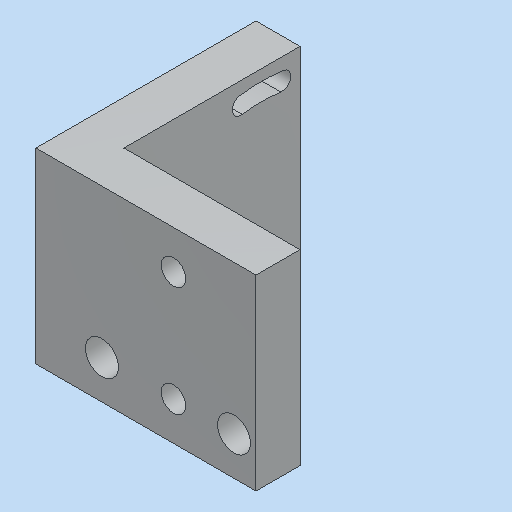
# Autodesk Inventor part: MM0948AN140_G01_118
Saved by Autodesk Inventor 2023.3 (Build 273359000, 359)
## iProperties
RuleStatus: InUse
Created: 2023-03-31
Part Number: MM0948AN140_G01_118
Material: 3.3206 AlMgSi0,5 - AW 6060
Description: =<RBPARTNOTITLE2>
Document SubType Name: Modeling
Designer: FH/Wi
Mass: 50.1036 g
Surface Area: 71.436 cm^2
Volume: 18.5569 cm^3
Density: 2.7 g/cm^3
Appearance: Aluminium AnP
AnP_Kategorie: 1
AnP_Material: =<Material>
MaxAbmaße: 34 x 40 x 40 (FM)
AnP_TemplVers: 20200821
RBDOCUMENTTYPE: DRF
RBDOCUMENTVERSION: 00
RBDRAWINGMAINSCALE: 1:1
RBDRAWINGMISSINGSPEC: --
RBDRAWINGVOLUME: --
RBDSV1: 0850
RBGBEDGESIN1: +0,5
RBGBEDGESIN2: +0,2
RBGBEDGESOUT1: -0,3
RBGBEDGESOUT2: -0,1
RBMATERIAL: =<Material>
RBMATMEETS: --
RBMATNO: =<Part Number>
RBPARTMADEOF: L 40 x 40 x 8 x 34 (FM)
RBPARTNO: SIEHE MNR
RBPARTNOTITLE1: manufactured part
RBPARTNOTITLE2: Anfertigungsteil
RBPARTSAFETYINDICATOR: --
RBSURFACE: anodised colourless
RBSURFACE2: eloxiert farblos
RBZEDGESNORM: ISO13715:2002-06
RBZGENDIMCLASS: m
RBZGENDIMNORM: ISO 2768-1:1989-11
RBZGENGEOCLASS: H
RBZGENGEONORM: ISO 2768-2:1989-11
RBZSURFACENORM: ISO13D2:2002-02
RBZTOLERANCENORM: ISO 14405-1:2010-12
Author: FH/Wi
Keywords: =<RBPARTMADEOF>
Comments: =<RBSURFACE2>
Revision Number: 01
Autodesk Inventor part; units mm, degrees
ref_plane "YZ Plane" through (0, 0, 0) normal (1, 0, 0) x (0, 1, 0)
ref_plane "XZ Plane" through (0, 0, 0) normal (0, 1, 0) x (-1, 0, 0)
ref_plane "XY Plane" through (0, 0, 0) normal (0, 0, 1) x (1, 0, 0)
sketch "Skizze1" plane through (0, 0, 0) normal (0, 0, 1) x (1, 0, 0)
  line L0 (0, 0) -> (40, 0)
  line L1 (40, 0) -> (40, 8)
  line L2 (8, 40) -> (0, 40)
  line L3 (0, 40) -> (0, 0)
  line L4 (8, 40) -> (8, 8)
  line L5 (8, 8) -> (40, 8)
  dimension "d0" = 40
  dimension "d1" = 40
  dimension "d10" = 8
  dimension "d11" = 8
  constraints: 12 end point, 2 parallel, 2 perpendicular, 1 horizontal, 1 vertical
  measures "d0" distance of L2.end L0.start
  measures "d1" distance of L0.start L0.end
  measures "d10" distance of L2.start L2.end
  measures "d11" distance of L0.end L1.end
extrude "Extrusion1" add sketch "Skizze1" along normal mid plane 34
sketch "Skizze2" plane through (0, 0, -17) normal (-1, 0, 0) x (0, 0, 1)
  circle A0 centre (3.6, 33) radius 1.6
  arc A1 (30.1392, 29.2702) -> (30.1392, 36.7298) centre (3.6, 33) ccw construction
  arc A2 (31.7236, 29.0475) -> (31.7236, 36.9525) centre (3.6, 33) ccw
  arc A3 (28.5548, 29.4928) -> (28.5548, 36.5072) centre (3.6, 33) ccw
  arc A4 (28.5548, 29.4928) -> (31.7236, 29.0475) centre (30.1392, 29.2702) ccw
  arc A5 (31.7236, 36.9525) -> (28.5548, 36.5072) centre (30.1392, 36.7298) ccw
  line L0 (3.6, 33) -> (30.4, 33) construction
  line L1 (0, 40) -> (34, 40) projected
  line L2 (3.6, 33) -> (30.1392, 36.7298) construction
  point P0 (17, 0)
  point P1 (17, 40)
  point P2 (17, 33)
  dimension "d4" = 3.2
  dimension "d5" = 7
  dimension "d6" = 26.8
  dimension "d7" = 8
  constraints: 11 point on circle, 6 centre point, 4 end point, 4 tangent, 2 midpoint, 1 coincident, 1 equal radius, 1 horizontal, 1 vertical alignment
  measures "d4" diameter of A0
  measures "d5" distance between parallel lines of L0 L1
  measures "d6" distance of L0.end L0.start
  measures "d7" angle of L0 L2
extrude "Extrusion2" cut sketch "Skizze2" against normal through all
sketch "Skizze3" plane through (8, 8, -17) normal (0, 1, 0) x (1, 0, 0)
  line L0 (32, 0) -> (32, -34) projected
  line L1 (32, -17) -> (23.3518, -17)
  point P0 (-8, -17)
  point P1 (17, -7)
  point P2 (17, -27)
  dimension "d19" = 15
  dimension "d20" = 20
  constraints: 2 end point, 1 horizontal, 1 midpoint, 1 symmetric about line
  measures "d19" distance from line of L0 point (17, -27)
  measures "d20" distance of point (17, -27) point (17, -7)
hole "Bohrung1" at (25, 8, -10) at (25, 8, 10) direction (0, -1, 0) diameter 4.5 end through all clearance for "Inbusschraube ISO 4762  versenkt" size "M4" standard "ISO"
sketch "Skizze4" plane through (8, 8, -17) normal (0, 1, 0) x (1, 0, 0)
  line L0 (0, 0) -> (0, -34) projected
  line L1 (32, 0) -> (32, -34) projected
  circle A0 centre (17, -7) radius 2.25 projected
  point P0 (-8, -17)
  point P1 (4, -7)
  point P2 (28, -7)
  dimension "d28" = 4
  dimension "d29" = 4
  constraints: 2 horizontal alignment
  measures "d28" distance from line of point (4, -7) L0
  measures "d29" distance from line of L1 point (28, -7)
hole "Bohrung2" at (12, 8, -10) at (36, 8, -10) direction (0, -1, 0) diameter 6 end through all
